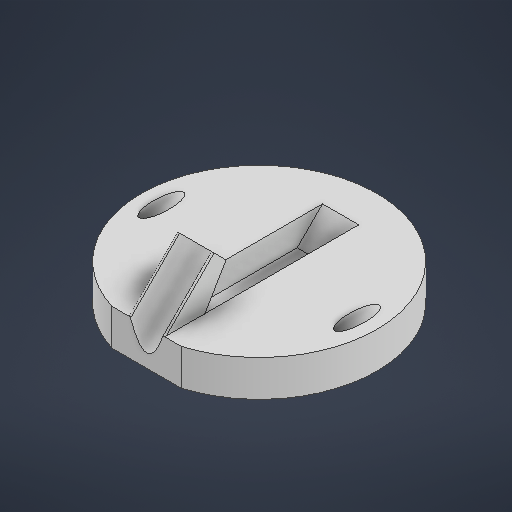
# Autodesk Inventor part: Landing Leg pad_4
Saved by Autodesk Inventor 2027 (Build 310192060, 192F)
## iProperties
Created: 2026-07-09
Part Number: Landing Leg pad_4
Material: Generic
Document SubType Name: Modeling
Designer: troop
Density: 1 g/cm^3
Appearance: Default
Author: troop
Autodesk Inventor part; units mm, degrees
sketch "Sketch1" plane through (0, 0, 0) normal (0, 1, 0) x (-1, 0, 0)
  circle A0 centre (0, 0) radius 41.275
  dimension "d16" = 82.55
  constraints: 1 centre point, 1 coincident
  measures "d16" diameter of A0
extrude "Extrusion1" add sketch "Sketch1" against normal blind 12.7
ref_plane "Work Plane1" through (41.275, 0, 41.275) normal (0, -0.7071068, 0.7071068) x (-1, 0, 0)
ref_plane "Work Plane3" through (-41.275, 0, 41.275) normal (0, -0.7071068, -0.7071068) x (1, 0, 0)
sketch "Sketch7" plane through (-41.275, 0, 41.275) normal (0, -0.7071068, -0.7071068) x (1, 0, 0)
  ellipse E0 centre (41.275, -29.185832) end of major axis (0, -29.185832) minor radius 29.185832
  line L0 (34.925, 0) -> (47.625, 0)
  line L1 (47.625, 0) -> (47.625, -25.4)
  line L2 (47.625, -25.4) -> (34.925, -25.4)
  line L3 (34.925, -25.4) -> (34.925, 0)
  point P0 (47.625, -0.347463)
  point P1 (34.925, -0.347463)
  dimension "d32" = 12.7
  dimension "d33" = 25.4
  dimension "d34" = 6.35
  constraints: 8 end point, 2 horizontal, 2 parallel, 1 perpendicular, 1 other
  measures "d32" distance of L1.end L2.end
  measures "d33" distance of L0.end L1.end
  measures "d34" distance from line of L3 point (41.275, -29.186)
extrude "Extrusion7" add sketch "Sketch7" along normal blind 10.16 contours L1 L2 L3 E0 picked at (41.275, -16.933333)
sketch "Sketch8" plane through (6.35, 17.960512, 23.314488) normal (0, 0.7071068, -0.7071068) x (-1, 0, 0)
  line L0 (0, -10.16) -> (0, -0.347463)
  line L1 (12.7, 0) -> (12.7, -10.16)
  line L2 (12.7, -10.16) -> (0, -10.16)
  line L3 (12.7, 0) -> (0, 0)
  spline S0 degree 2 poles (0, 0) (6.35, -13.97) (12.7, 0) knots 0 0 0 1 1 1
  line L4 (0, 0) -> (0, 0)
  line L5 (0, 0) -> (12.7, 0)
  line L6 (12.7, 0) -> (12.7, 0)
  ellipse E0 centre (6.35, -29.185832) end of major axis (47.625, -29.185832) minor radius 29.185832 (0, -0.347463) -> (12.7, -0.347463) ccw
  point P0 (6.35, -6.985)
  point P1 (6.35, 0)
  point P2 (0, -0.347463)
  dimension "d39" = 0
  dimension "d40" = 0
  dimension "d41" = 0
  dimension "d42" = 3.175
  dimension "d96" = 6.985
  constraints: 6 end point, 2 point on line, 1 collinear, 1 midpoint, 1 perpendicular, 1 vertical, 4 other
  measures "d39" horizontal distance of point (6.35, 0) point (6.35, -6.985)
  measures "d40" distance from line of L3 L6.end
  measures "d41" distance from line of L3 L4.start
  measures "d42" distance from line of L2 point (6.35, -6.985)
  measures "d96" vertical distance of L1.start point (6.35, -6.985)
extrude "Extrusion8" cut sketch "Sketch8" against normal blind 76.2 contours S0 L3
fillet "Fillet1" radius 0.381 1 edges at (6.35, 9.1031, 32.1719)
fillet "Fillet2" radius 0.381 1 edges at (-6.35, 9.1031, 32.1719)
sketch "Sketch9" plane through (0, 0, 0) normal (0, 1, 0) x (1, 0, 0)
  line L0 (6.35, 28.575) -> (-6.35, 28.575)
  line L1 (-6.35, 28.575) -> (-6.35, -25.4)
  line L2 (-6.35, -25.4) -> (6.35, -25.4)
  line L3 (6.35, -25.4) -> (6.35, 28.575)
  arc A0 (6.197763, -40.807026) -> (-6.197763, -40.807026) centre (0, 0) ccw
  line L4 (-12.460112, -39.448003) -> (12.939888, -39.448003)
  circle A1 centre (0, 0) radius 41.275
  arc A2 (-12.144161, -39.448003) -> (12.144161, -39.448003) centre (0, 0) ccw
  point P0 (0, 41.275)
  point P1 (0, -41.275)
  point P2 (-12.144161, -39.448003)
  dimension "d48" = 12.7
  dimension "d49" = 6.35
  dimension "d50" = 12.7
  dimension "d51" = 25.4
  dimension "d54" = 25.4
  dimension "d55" = 39.448
  dimension "d56" = 12.46011
  constraints: 10 end point, 7 point on circle, 2 horizontal, 2 parallel, 2 point on line, 1 centre point, 1 perpendicular
  measures "d48" distance of L0.start L0.end
  measures "d49" distance from line of point (0, 0) L1
  measures "d50" distance from line of point (0, 41.275) L0
  measures "d51" distance from line of point (0, 0) L2
  measures "d54" distance of L4.start L4.end
  measures "d55" distance from line of point (0, 0) L4
  measures "d56" horizontal distance of point (0, -41.275) L4.start
extrude "Extrusion9" cut sketch "Sketch9" against normal blind 8.89 contours L3 L2 L1 L0
extrude "Extrusion10" cut sketch "Sketch9" against normal blind 12.7 contours A1 A0 L4
sketch "Sketch10" plane through (-6.35, 0, 25.4) normal (1, 0, 0) x (0, 0, -1)
  line L0 (0, 0) -> (0, -8.89) projected
  line L1 (0, 0) -> (-8.89, -8.89)
  line L2 (-8.89, -8.89) -> (0, -8.89)
  line L3 (53.975, 0) -> (53.975, -8.89) projected
  line L4 (53.975, 0) -> (45.085, -8.89)
  line L5 (0, -8.89) -> (53.975, -8.89) projected
  line L6 (53.975, 0) -> (53.975, -8.89) projected
  line L7 (53.975, -8.89) -> (53.975, 0)
  point P0 (25.4, 0)
  dimension "d59" = 45
  dimension "d90" = 45
  constraints: 8 end point, 1 perpendicular, 1 point on line, 1 vertical
  measures "d59" angle of L1 L0
  measures "d90" angle of L3 L4
extrude "Extrusion11" cut sketch "Sketch10" along normal blind 12.7 contours L0 L2 L1
fillet "Fillet4" radius 0.762 1 edges at (0, -8.89, 34.29)
sketch "Sketch11" plane through (0, 0, 0) normal (1, 0, 0) x (0, 1, 0)
  line L0 (12.572359, 17.926334) -> (10.776307, 16.130283)
  line L1 (10.776307, 16.130283) -> (0, 25.4)
  line L2 (10.776307, 16.130283) -> (0, 26.90659)
  line L3 (0, -41.275) -> (0, 39.448003)
  line L4 (0, 26.90659) -> (0, 25.4)
  point P0 (0, 0)
  constraints: 6 end point, 1 collinear, 1 point on line
extrude "Extrusion12" add sketch "Sketch11" along normal mid plane 12.7
ref_plane "Work Plane5" through (0, 13.021371, 18.375347) normal (0, 0.7071068, -0.7071068) x (-1, 0, 0)
ref_plane "Work Plane8" through (-6.35, 28.150931, -31.606102) normal (0, -0.3420201, 0.9396926) x (1, 0, 0)
ref_plane "Work Plane7" through (-6.35, 10.776307, 16.130283) normal (0, -0.3420201, 0.9396926) x (1, 0, 0)
sketch "Sketch14" plane through (0, 0, 0) normal (0, 1, 0) x (1, 0, 0)
  circle A0 centre (-34.29, 0) radius 2.675
  circle A1 centre (34.29, 0) radius 2.675
  point P0 (0, 0)
  dimension "d82" = 5.35
  dimension "d83" = 34.29
  dimension "d84" = 5.35
  dimension "d85" = 34.29
  constraints: 2 centre point
  measures "d82" diameter of A0
  measures "d83" distance of point (0, 0) A0.centre
  measures "d84" diameter of A1
  measures "d85" distance of point (0, 0) A1.centre
sketch "Sketch15" plane through (-6.35, 28.150931, -31.606102) normal (0, -0.3420201, 0.9396926) x (1, 0, 0)
  circle A0 centre (40.64, -15.643298) radius 2.675
  circle A1 centre (-27.94, -15.643298) radius 2.675
  point P0 (6.35, -15.643298)
  dimension "d86" = 5.35
  dimension "d87" = 5.35
  constraints: 2 centre point, 2 coincident
  measures "d86" diameter of A0
  measures "d87" diameter of A1
extrude "Extrusion14" cut sketch "Sketch15" along normal blind 53.975
extrude "Extrusion15" add sketch "Sketch10" along normal blind 12.7 contours L3 L5 L4
sketch "Sketch16" plane through (6.35, 0, 38.915957) normal (1, 0, 0) x (0, 0, -1)
  line L0 (16.780991, 16.780991) -> (22.785675, 10.776307)
  line L1 (22.785675, 10.776307) -> (20.989623, 12.572359)
  line L2 (22.785675, 10.776307) -> (13.515957, 0)
  line L3 (20.989623, 12.572359) -> (13.515957, 0)
  line L4 (13.515957, 0) -> (22.785675, 10.776307)
  point P0 (38.915957, 0)
  dimension "d93" = 2.54
  constraints: 6 end point, 1 point on line
  measures "d93" distance of L0.end L1.end
extrude "Extrusion16" cut sketch "Sketch16" against normal blind 12.7
body "Solid1"
